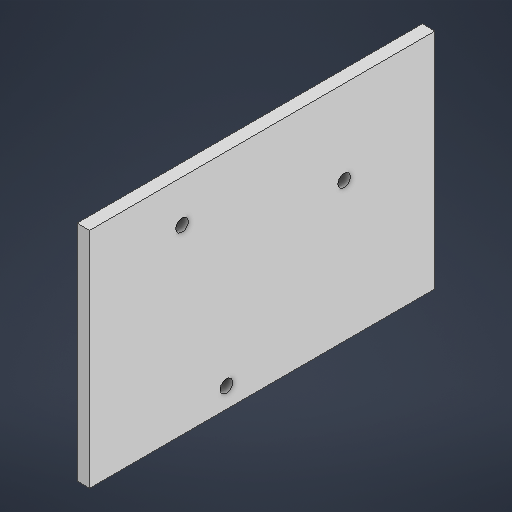
# Autodesk Inventor part: motor support1
Saved by Autodesk Inventor 2025.2 (Build 292293000, 293)
## iProperties
Created: 2024-12-25
Part Number: motor support1
Material: Generic
Document SubType Name: Modeling
Designer: user
Density: 1 g/cm^3
Appearance: Default
Author: user
Autodesk Inventor part; units mm, degrees
ref_plane "YZ Plane" through (0, 0, 0) normal (1, 0, 0) x (0, 1, 0)
ref_plane "XZ Plane" through (0, 0, 0) normal (0, 1, 0) x (-1, 0, 0)
ref_plane "Work Plane13" through (-46.8502, 45, 147) normal (-1, 0, 0) x (0, 0, 1)
sketch "Sketch10" plane through (-46.8502, 45, 147) normal (-1, 0, 0) x (0, 0, 1)
  line L0 (63.7512, -45) -> (-73.1132, -45)
  line L1 (-73.1132, -45) -> (-73.1132, 43.5)
  line L2 (-73.1132, 43.5) -> (63.7512, 43.5)
  line L3 (63.7512, 43.5) -> (63.7512, -45)
  arc A0 (15.9668, -40.4637) -> (-15.9668, -40.4637) centre (0, 0) ccw projected
  circle A1 centre (27.1351, 27.0288) radius 2.5 projected
  circle A2 centre (-37.1137, 10.2366) radius 2.5 projected
  circle A3 centre (9.5532, -37.0084) radius 2.5 projected
  point P0 (-147, -45)
  constraints: 8 end point, 2 parallel, 1 horizontal, 1 perpendicular, 1 tangent
extrude "Extrusion9" add sketch "Sketch10" along normal blind 5
body "Solid1"
body "Solid2"
